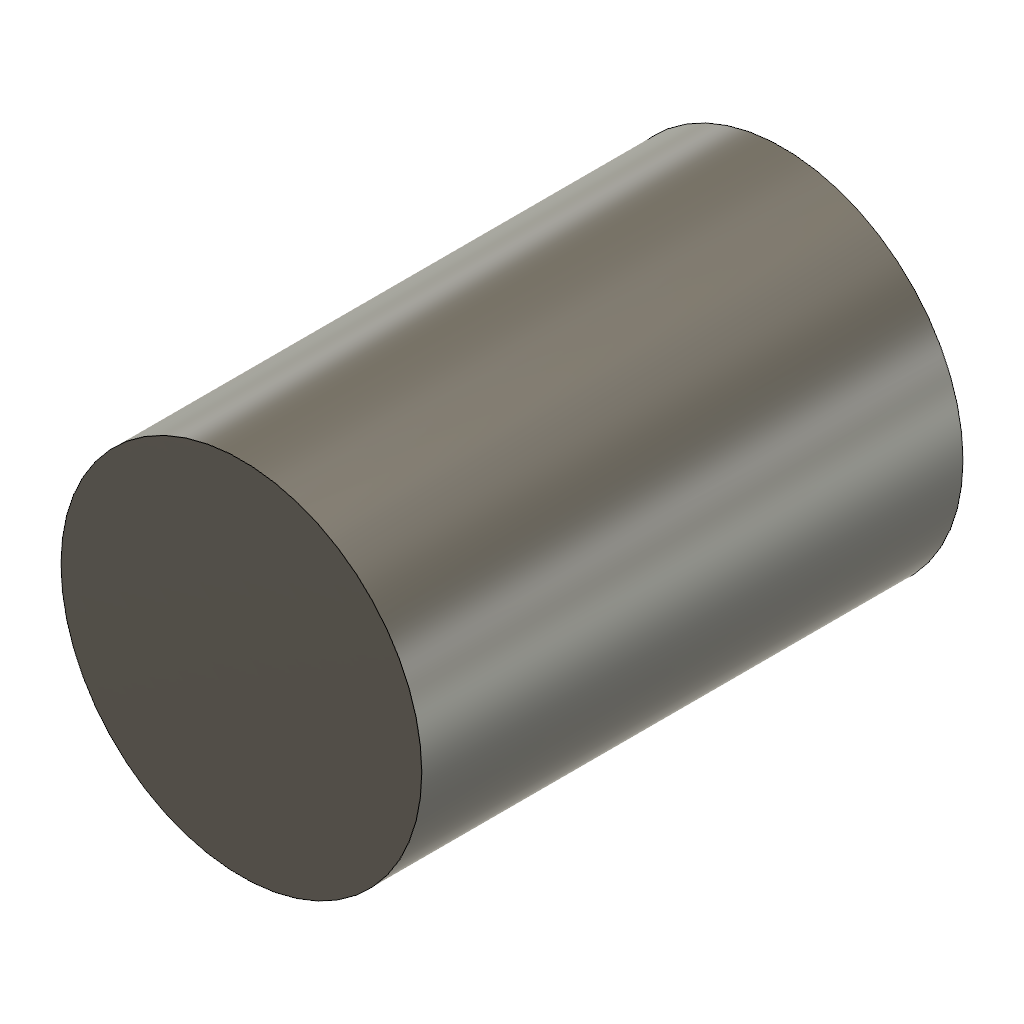
two_sided_mixed (Autodesk Fusion 360 design; units mm, degrees)
part number: 2026-10-20-18-12-39-846
Autodesk Fusion 360 part; units mm, degrees
sketch "SeedProfile" plane through (0, 0, 0) normal (0, 0, 1) x (1, 0, 0)
  circle A0 centre (0, 0) radius 20
extrude "SeedExtrusion" add sketch "SeedProfile" along normal mid plane 60
sketch "ProbeProfile" plane through (0, 0, 0) normal (0, 0, 1) x (1, 0, 0)
  circle A0 centre (0, 0) radius 10
extrude "ProbeExtrusion" cut sketch "ProbeProfile" along normal blind 11 and the other way through all
